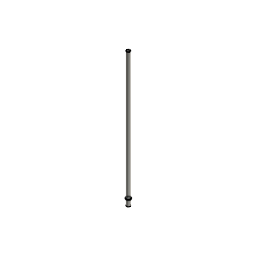
Metalic Tube 2 (Autodesk Fusion 360 design; units mm, degrees)
part number: 2025-11-17-16-45-31-068
Autodesk Fusion 360 part; units mm, degrees
sketch "Sketch1" plane through (0, 0, 43) normal (0, 0, -1) x (1, 0, 0)
  circle A0 centre (-5.0641, -0.0619) radius 2.5
  circle A1 centre (-5.0641, -0.0619) radius 3
sketch "Sketch2" plane through (0, 0, 43) normal (0, 0, -1) x (-1, 0, 0)
  circle A0 centre (5.0641, 0.0619) radius 2.5
  circle A1 centre (5.0641, 0.0619) radius 2.5
  circle A2 centre (5.0641, 0.0619) radius 2
  dimension "d173" = 5
  dimension "d174" = 4
  constraint concentric A0 A1
  constraint concentric A1 A2
  measures "d173" diameter of A0
  measures "d174" diameter of A2
extrude "Extrude1" add sketch "Sketch2" along normal blind 9 and the other way blind 180
